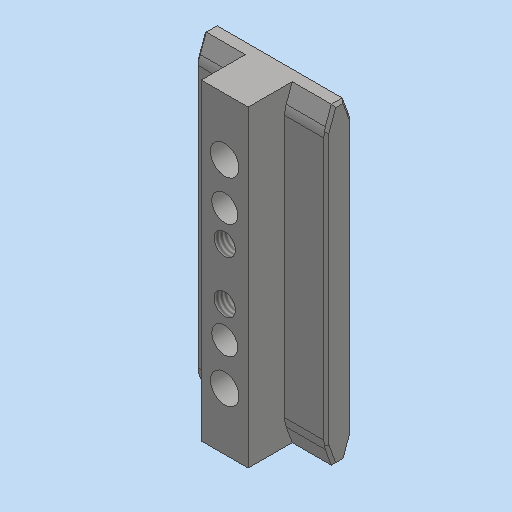
# Autodesk Inventor part: MM0948AN160_G01_108
Saved by Autodesk Inventor 2023.3 (Build 273359000, 359)
## iProperties
RuleStatus: InUse
Created: 2023-03-23
Part Number: MM0948AN160_G01_108
Material: 1.2842 90MnCrV8
Description: =<RBPARTNOTITLE2>
Document SubType Name: Modeling
Designer: FH/Wi
Mass: 72.0864 g
Surface Area: 56.2545 cm^2
Volume: 9.18298 cm^3
Density: 7.85 g/cm^3
Appearance: Stahl - normal AnP
AnP_Kategorie: 1
AnP_Material: =<Material>
MaxAbmaße: 60 x 12 x 25 (FM)
AnP_TemplVers: 20200821
RBDOCUMENTTYPE: DRF
RBDOCUMENTVERSION: 00
RBDRAWINGMAINSCALE: 1:1
RBDRAWINGMISSINGSPEC: --
RBDRAWINGVOLUME: --
RBDSV1: 0850
RBGBEDGESIN1: +0,5
RBGBEDGESIN2: +0,2
RBGBEDGESOUT1: -0,3
RBGBEDGESOUT2: -0,1
RBMATERIAL: =<Material>
RBMATMEETS: --
RBMATNO: =<Part Number>
RBPARTMADEOF: 60 x 12 x 25 (FM)
RBPARTNO: SIEHE MNR
RBPARTNOTITLE1: manufactured part
RBPARTNOTITLE2: Anfertigungsteil
RBPARTSAFETYINDICATOR: --
RBSURFACE: plasma nitrided 550 HV, Nht 0,2 + 0,1
RBSURFACE2: plasmanitriert 550 HV, Nht 0,2 + 0,1
RBZEDGESNORM: ISO13715:2002-06
RBZGENDIMCLASS: m
RBZGENDIMNORM: ISO 2768-1:1989-11
RBZGENGEOCLASS: H
RBZGENGEONORM: ISO 2768-2:1989-11
RBZSURFACENORM: ISO13D2:2002-02
RBZTOLERANCENORM: ISO 14405-1:2010-12
AnP_Kommentar_aktuell: =<Comments>
AnP_Material_aktuell: =<Material>
Author: FH/Wi
Keywords: =<RBPARTMADEOF>
Comments: =<RBSURFACE2>
Revision Number: 01
Autodesk Inventor part; units mm, degrees
ref_plane "YZ Plane" through (0, 0, 0) normal (1, 0, 0) x (0, 1, 0)
ref_plane "XZ Plane" through (0, 0, 0) normal (0, 1, 0) x (-1, 0, 0)
ref_plane "XY Plane" through (0, 0, 0) normal (0, 0, 1) x (1, 0, 0)
sketch "Skizze1" plane through (0, 0, 0) normal (0, 0, 1) x (1, 0, 0)
  line L0 (-12.5, 12) -> (12.5, 12)
  line L1 (12.5, 12) -> (12.5, 7)
  line L2 (-12.5, 7) -> (-12.5, 12)
  line L3 (4.5, 7) -> (4.5, 0)
  line L4 (4.5, 0) -> (-4.5, 0)
  line L5 (-4.5, 0) -> (-4.5, 7)
  line L6 (-12.5, 9.5) -> (8.7908, 9.5) construction
  line L7 (12.5, 7) -> (4.5, 7)
  line L8 (-4.5, 7) -> (-12.5, 7)
  point P0 (0, 0)
  point P1 (0, 0)
  dimension "d0" = 5
  dimension "d1" = 9
  dimension "d2" = 25
  dimension "d3" = 9.5
  constraints: 18 end point, 4 parallel, 2 collinear, 2 horizontal, 2 midpoint, 1 coincident, 1 perpendicular, 1 vertical
  measures "d0" distance of L2.start L0.start
  measures "d1" distance of L3.end L4.end
  measures "d2" distance of L0.start L0.end
  measures "d3" distance between parallel lines of L4 L6
extrude "Extrusion1" add sketch "Skizze1" along normal mid plane 60
sketch "Skizze2" plane through (-12.5, 12, 30) normal (0, 1, 0) x (1, 0, 0)
  line L0 (12.5, 49) -> (12.5, 11)
  line L1 (0, 60) -> (25, 60) projected
  point P0 (12.5, 30)
  point P1 (12.5, 30)
  dimension "d13" = 11
  constraints: 2 end point, 1 coincident, 1 midpoint, 1 vertical
  measures "d13" distance from line of L0.start L1
hole "Bohrung1" at (0, 12, 19) at (0, 12, -19) direction (0, -1, 0) diameter 5.5 end through all counterbore diameter 10 counterbore depth 4.2 clearance for "Flachk.Schr. DIN 6912  versenkt" size "M5" standard "ISO"
sketch "Skizze3" plane through (-4.5, 0, 30) normal (0, -1, 0) x (1, 0, 0)
  circle A0 centre (4.5, -11) radius 2.75 projected
  line L0 (4.5, -19) -> (4.5, -41)
  point P0 (4.5, -30)
  point P1 (4.5, -30)
  dimension "d27" = 8
  constraints: 2 end point, 1 coincident, 1 midpoint, 1 vertical
  measures "d27" distance of L0.start A0.centre
hole "Bohrung2" at (0, 0, 11) at (0, 0, -11) direction (0, 1, 0) diameter 5 end through all
chamfer "Fase3" distance 4 angle 20 1 edges at (0, 12, 30) measured on face at (-9.8917, 12, -5.7423)
chamfer "Fase4" distance 4 angle 20 1 edges at (-8.5, 7, 30) measured on face at (-7.1667, 7, 10)
chamfer "Fase5" distance 4 angle 20 1 edges at (8.5, 7, 30) measured on face at (7.1667, 7, -10)
chamfer "Fase6" distance 4 angle 20 1 edges at (0, 12, -30) measured on face at (-9.8917, 12, -7.0757)
chamfer "Fase7" distance 4 angle 20 1 edges at (8.5, 7, -30) measured on face at (7.1667, 7, -11.3333)
chamfer "Fase8" distance 4 angle 20 1 edges at (-8.5, 7, -30) measured on face at (-9.8333, 7, -11.3333)
chamfer "Fase9" distance 0.5 angle 45 16 edges at (12.5, 11.2721, 28) (12.5, 9.5, 30) (12.5, 12, 0) (12.5, 7.7279, 28) (12.5, 7, 0) (12.5, 7.7279, -28) (12.5, 9.5, -30) (12.5, 11.2721, -28) (-12.5, 7.7279, -28) (-12.5, 9.5, -30) (-12.5, 11.2721, -28) (-12.5, 12, 0) (-12.5, 7, 0) (-12.5, 7.7279, 28) (-12.5, 9.5, 30) (-12.5, 11.2721, 28)
sketch "Skizze4" plane through (-12, 12, 26) normal (0, 1, 0) x (1, 0, 0)
  line L0 (12, 68) -> (12, -16) projected
  line L1 (29.5, 26) -> (-5.5, 26) projected
  point P0 (12, 26)
  point P1 (12, 31)
  point P2 (12, 21)
  dimension "d49" = 10
  constraints: 2 point on line, 1 symmetric about line
  measures "d49" distance of point (12, 21) point (12, 31)
hole "Bohrung3" at (0, 12, -5) at (0, 12, 5) direction (0, -1, 0) diameter 4.134 end through all thread size "M5x0.8" designation "M5" class "6H" standard "ISO Metric profile"
fillet "Rundung1" radius 5 6 edges at (8.25, 7, 26) (0, 12, 26) (-8.25, 7, 26) (-8.25, 7, -26) (0, 12, -26) (8.25, 7, -26)
equation "\"d31\" = d28"
equation "\"d33\" = d30"
equation "\"d34\" = d28"
equation "\"d36\" = d30"
equation "\"d37\" = d28"
equation "\"d39\" = d30"
equation "\"d40\" = d28"
equation "\"d42\" = d30"
equation "\"d43\" = d28"
equation "\"d45\" = d30"
equation "\"d48\" = d30"
equation "\"d28\" = 4"
equation "\"d30\" = 20deg"
